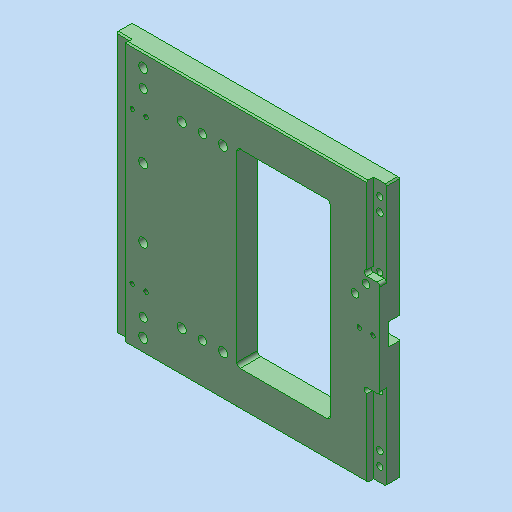
# Autodesk Inventor part: MM0937AN100_G16_103
Saved by Autodesk Inventor 2023.3 (Build 273359000, 359)
## iProperties
Created: 2018-10-25
Part Number: MM0937AN100_G16_103
Material: 1.2842 90MnCrV8
Document SubType Name: Modeling
Designer: Rose
Density: 7.85 g/cm^3
Appearance: Grün-H
Mass: 2925.7 g
Surface Area: 800.514 cm^2
Volume: 372.7 cm^3
Description: =<RBPARTNOTITLE2>
RBMATERIAL: =<Material>
RBMATNO: =<Part Number>
RBPARTMADEOF: Präzi Fl.190 x 15 x 207 (FM)
RBPARTNOTITLE1: manufactured part
RBPARTNOTITLE2: Anfertigungsteil
MaxAbmaße: 190 x 15 x 207 (FM)
RBDRAWINGMISSINGSPEC: --
AnP_Kategorie: 1
RBSURFACE: chemically nickel-coated
AnP_Material: =<Material>
RBSURFACE2: chem. vernickelt
Author: Rose
Keywords: =<RBPARTMADEOF>
Comments: =<RBSURFACE2>
Revision Number: 01
Autodesk Inventor part; units mm, degrees
ref_plane "YZ Plane" through (0, 0, 0) normal (1, 0, 0) x (0, 1, 0)
ref_plane "XZ Plane" through (0, 0, 0) normal (0, 1, 0) x (-1, 0, 0)
ref_plane "XY Plane" through (0, 0, 0) normal (0, 0, 1) x (1, 0, 0)
sketch "Skizze1" plane through (0, 0, 0) normal (0, 0, 1) x (1, 0, 0)
  line L0 (0, 18) -> (0, -3) projected
  line L1 (-97.4, 0) -> (192.4, 0) projected
  line L2 (151, 0) -> (-41, 0)
  line L3 (-41, 0) -> (-41.2, 0.2)
  line L4 (-41.2, 0.2) -> (-56, 0.2)
  line L5 (-56, 0.2) -> (-56, 5.8)
  line L6 (-44, 15) -> (151, 15)
  line L7 (151, 15) -> (151, 0)
  line L8 (-56, 5.8) -> (-44, 5.8)
  line L9 (-44, 5.8) -> (-44, 15)
  line L10 (151, 0) -> (151, 0)
  line L11 (-44, 5.8) -> (-44, 0)
  line L12 (-44, 0) -> (-41, 0)
  dimension "d0" = 15
  dimension "d1" = 151
  dimension "d89" = 45
  dimension "d105" = 90
  dimension "d137" = 41
  dimension "d138" = 44
  dimension "d145" = 56
  dimension "d146" = 9.2
  dimension "d148" = 5.6
  constraints: 22 end point, 4 point on line, 3 perpendicular, 2 parallel, 1 horizontal
  measures "d0" distance between parallel lines of L1 L6
  measures "d1" distance between parallel lines of L7 L0
  measures "d89" angle of L1 L3
  measures "d105" angle of L6 L9
  measures "d137" distance from line of L0 L2.end
  measures "d138" distance from line of L0 L8.end
  measures "d145" distance between parallel lines of L0 L5
  measures "d146" distance between parallel lines of L8 L6
  measures "d148" distance between parallel lines of L4 L8
extrude "Extrusion1" add sketch "Skizze1" along normal mid plane 190 contours L6 L7 L1 L0 | L0 L1 L3 L4 L11 L9 L6 | L1 L11 L4 L3
sketch "Skizze12" plane through (151, 0, 95) normal (1, 0, 0) x (0, 0, -1)
  line L0 (190, 15) -> (0, 15) projected
  line L1 (0, 0) -> (0, 15) projected
  line L2 (190, 0) -> (0, 0) projected
  line L3 (190, 15) -> (190, 0) projected
  line L4 (0, 0) -> (60, 0)
  line L5 (60, 0) -> (60, 5)
  line L6 (60, 5) -> (0, 5)
  line L7 (0, 5) -> (0, 0)
  line L8 (190, 0) -> (130, 0)
  line L9 (130, 0) -> (130, 5)
  line L10 (130, 5) -> (190, 5)
  line L11 (190, 5) -> (190, 0)
  point P0 (95, 0)
  point P1 (130, 0)
  point P2 (60, 0)
  dimension "d155" = 60
  dimension "d156" = 5
  dimension "d157" = 60
  dimension "d158" = 5
  constraints: 16 end point, 4 parallel, 2 horizontal, 2 perpendicular
  measures "d155" distance of L6.end L5.end
  measures "d156" distance of L5.end L4.end
  measures "d157" distance of L9.end L10.end
  measures "d158" distance of L8.end L9.end
extrude "Extrusion5" cut sketch "Skizze12" against normal blind 9.5 contours L3 L2 L9 L10 | L6 L5 L2 L1
sketch "Skizze2" plane through (-56, 15, 95) normal (0, 1, 0) x (1, 0, 0)
  line L0 (246, 95) -> (-27, 95) projected
  line L1 (105.5, 26) -> (168.5, 26)
  line L2 (103, 28.5) -> (103, 161.5)
  line L3 (105.5, 164) -> (168.5, 164)
  line L4 (56, 228) -> (56, -38) projected
  arc A0 (105.5, 164) -> (103, 161.5) centre (105.5, 161.5) ccw
  arc A1 (103, 28.5) -> (105.5, 26) centre (105.5, 28.5) ccw
  arc A2 (171, 161.5) -> (168.5, 164) centre (168.5, 161.5) ccw
  arc A3 (168.5, 26) -> (171, 28.5) centre (168.5, 28.5) ccw
  line L5 (171, 161.5) -> (171, 28.5)
  dimension "d15" = 138
  dimension "d63" = 2.5
  dimension "d117" = 47
  dimension "d120" = 115
  dimension "d124" = 2.5
  constraints: 8 end point, 8 point on circle, 8 tangent, 4 centre point, 2 equal radius, 1 perpendicular, 1 other
  measures "d15" distance between parallel lines of L1 L3
  measures "d63" radius of A2
  measures "d117" distance between parallel lines of L4 L2
  measures "d120" distance between parallel lines of L5 L4
  measures "d124" radius of A1
extrude "Extrusion2" cut sketch "Skizze2" against normal through all
sketch "Skizze3" plane through (-56, 15, -95) normal (0, 1, 0) x (1, 0, 0)
  line L0 (56, 38) -> (56, -228) projected
  line L1 (246, -95) -> (-27, -95) projected
  line L2 (63, -30) -> (93, -30)
  point P0 (93, -160)
  point P1 (63, -160)
  dimension "d22" = 7
  dimension "d23" = 130
  dimension "d118" = 30
  constraints: 2 end point, 2 symmetric about line, 1 coincident, 1 horizontal
  measures "d22" distance from line of L0 L2.start
  measures "d23" distance of point (63, -160) L2.start
  measures "d118" distance of L2.start L2.end
hole "Bohrung1" at (37, 15, -65) at (37, 15, 65) at (7, 15, -65) at (7, 15, 65) direction (0, -1, 0) diameter 6.6 end through all counterbore diameter 11 counterbore depth 6.5
sketch "Skizze4" plane through (-56, 15, -95) normal (0, 1, 0) x (1, 0, 0)
  line L0 (246, -95) -> (-27, -95) projected
  line L1 (56, 38) -> (56, -228) projected
  line L2 (27, -40) -> (37, -40)
  line L3 (27, -150) -> (37, -150)
  line L4 (192, -95) -> (202, -95)
  dimension "d31" = 10
  dimension "d33" = 19
  dimension "d34" = 110
  dimension "d64" = 136
  constraints: 6 coincident, 6 end point, 4 parallel, 1 perpendicular, 1 point on line, 1 symmetric about line
  measures "d31" distance of L2.start L2.end
  measures "d33" distance from line of L1 point (37, -40)
  measures "d34" distance of point (27, -150) point (27, -40)
  measures "d64" distance from line of point (192, -95) L1
hole "Bohrung2" at (-29, 15, -55) at (-19, 15, -55) at (136, 15, 0) at (146, 15, 0) at (-19, 15, 55) at (-29, 15, 55) direction (0, -1, 0) diameter 3.242 end through all thread size "M4x0.7" designation "M4" class "6H" standard "ISO Metric profile"
sketch "Skizze5" plane through (-56, 15, -95) normal (0, 1, 0) x (1, 0, 0)
  line L0 (56, 38) -> (56, -228) projected
  circle A0 centre (37, -40) radius 1.621 projected
  circle A1 centre (192, -95) radius 1.621 projected
  circle A2 centre (37, -150) radius 1.621 projected
  line L1 (37, -40) -> (53, -40) construction
  line L2 (192, -95) -> (176, -95) construction
  line L3 (37, -150) -> (53, -150) construction
  line L4 (12, -158) -> (50, -158)
  line L5 (53, -155) -> (53, -145)
  line L6 (50, -142) -> (12, -142)
  line L7 (179, -103) -> (207, -103)
  line L8 (207, -87) -> (179, -87)
  line L9 (176, -90) -> (176, -100)
  line L10 (12, -48) -> (50, -48)
  line L11 (53, -45) -> (53, -35)
  line L12 (50, -32) -> (12, -32)
  arc A3 (50, -48) -> (53, -45) centre (50, -45) ccw
  arc A4 (53, -35) -> (50, -32) centre (50, -35) ccw
  arc A5 (176, -100) -> (179, -103) centre (179, -100) ccw
  arc A6 (179, -87) -> (176, -90) centre (179, -90) ccw
  arc A7 (53, -145) -> (50, -142) centre (50, -145) ccw
  arc A8 (50, -158) -> (53, -155) centre (50, -155) ccw
  line L13 (207, 0) -> (207, -190) projected
  line L14 (9, -35) -> (9, -45)
  line L15 (9, -145) -> (9, -155)
  arc A9 (12, -32) -> (9, -35) centre (12, -35) ccw
  arc A10 (9, -45) -> (12, -48) centre (12, -45) ccw
  arc A11 (12, -142) -> (9, -145) centre (12, -145) ccw
  arc A12 (9, -155) -> (12, -158) centre (12, -155) ccw
  dimension "d65" = 16
  dimension "d66" = 16
  dimension "d67" = 3
  dimension "d140" = 28
  constraints: 28 end point, 20 point on circle, 20 tangent, 10 centre point, 9 equal radius, 7 perpendicular, 5 parallel, 4 equal length, 3 horizontal, 3 midpoint, 2 point on line, 1 collinear
  measures "d65" distance between parallel lines of L10 L12
  measures "d66" distance of L1.start L1.end
  measures "d67" radius of A3
  measures "d140" distance from line of L14 L1.start
extrude "Extrusion3" cut sketch "Skizze5" against normal blind 8.5
sketch "Skizze6" plane through (-56, 15, -95) normal (0, 1, 0) x (1, 0, 0)
  line L0 (56, 38) -> (56, -228) projected
  line L1 (246, -95) -> (-27, -95) projected
  point P0 (20, -60)
  point P1 (20, -130)
  dimension "d47" = 70
  dimension "d68" = 36
  constraints: 1 symmetric about line
  measures "d47" distance of point (20, -130) point (20, -60)
  measures "d68" distance from line of L0 point (20, -60)
hole "Bohrung3" at (-36, 15, -35) at (-36, 15, 35) direction (0, -1, 0) diameter 9 depth 9 counterbore diameter 17 counterbore depth 5
sketch "Skizze10" plane through (-41, 0, 95) normal (0, -1, 0) x (1, 0, 0)
  line L0 (-42, -95) -> (231, -95) projected
  circle A0 centre (48, -30) radius 3.3 projected
  circle A1 centre (78, -30) radius 3.3 projected
  line L1 (48, -30) -> (78, -30)
  point P0 (63, -30)
  point P1 (63, -160)
  point P2 (12, -10)
  point P3 (63, -30)
  constraints: 2 end point, 1 coincident, 1 horizontal, 1 midpoint, 1 symmetric about line
hole "Bohrung6" at (22, 0, 65) at (22, 0, -65) direction (0, 1, 0) diameter 5.5 end through all counterbore diameter 6 counterbore depth 13
sketch "Skizze11" plane through (-44, 15, 95) normal (0, 1, 0) x (1, 0, 0)
  line L0 (234, 95) -> (-39, 95) projected
  line L1 (44, 228) -> (44, -38) projected
  point P0 (177, 75)
  point P1 (185, 65)
  dimension "d126" = 20
  dimension "d127" = 10
  dimension "d128" = 8
  dimension "d149" = 133
  measures "d126" distance from line of L0 point (177, 75)
  measures "d127" vertical distance of point (185, 65) point (177, 75)
  measures "d128" horizontal distance of point (185, 65) point (177, 75)
  measures "d149" distance from line of point (177, 75) L1
hole "Bohrung7" at (133, 15, 20) at (141, 15, 30) direction (0, -1, 0) diameter 5.5 end through all counterbore diameter 10 counterbore depth 5.5
chamfer "Fase1" distance 1 angle 45 6 edges at (151, 10, 95) (151, 10, -95) (53.5, 15, 95) (48.75, 0, 95) (53.5, 15, -95) (48.75, 0, -95)
chamfer "Fase2" distance 1 angle 45 5 edges at (151, 15, 51) (151, 15, -51) (-44, 15, 0) (-44, 7.5, 95) (-44, 7.5, -95)
chamfer "Fase3" distance 0.5 angle 45 2 edges at (-27.5709, 15, -36.0955) (-27.5709, 15, 36.0955)
sketch "Skizze13" plane through (-43, 15, 94) normal (0, 1, 0) x (1, 0, 0)
  line L0 (194, 0) -> (194, 86) projected
  point P0 (43, 94)
  point P1 (189, 9)
  point P2 (189, 56.6)
  point P3 (189, 131.4)
  point P4 (189, 179)
  dimension "d161" = 5
  dimension "d162" = 37.4
  dimension "d163" = 37.4
  dimension "d164" = 85
  dimension "d165" = 85
  constraints: 3 vertical alignment
  measures "d161" distance from line of point (189, 9) L0
  measures "d162" vertical distance of point (189, 56.6) point (43, 94)
  measures "d163" vertical distance of point (189, 131.4) point (43, 94)
  measures "d164" vertical distance of point (189, 179) point (43, 94)
  measures "d165" vertical distance of point (189, 9) point (43, 94)
hole "Bohrung8" at (146, 15, 85) at (146, 15, 37.4) at (146, 15, -37.4) at (146, 15, -85) direction (0, -1, 0) diameter 4.5 end through all counterbore diameter 8 counterbore depth 4.6 clearance for "Inbusschraube ISO 4762  versenkt" size "M4" standard "ISO"
sketch "Skizze14" plane through (141.5, 5, 35) normal (0, -1, 0) x (1, 0, 0)
  circle A0 centre (4.5, 50) radius 2.25 projected
  point P0 (-141.5, -35)
  point P1 (4.5, 40)
  point P2 (4.5, -110)
  dimension "d173" = 75
  dimension "d174" = 75
  constraints: 2 vertical alignment
  measures "d173" vertical distance of point (4.5, 40) point (-141.5, -35)
  measures "d174" vertical distance of point (4.5, -110) point (-141.5, -35)
hole "Bohrung9" at (146, 5, 75) at (146, 5, -75) direction (0, 1, 0) diameter 4 end through all counterbore diameter 5 counterbore depth 6
fillet "Rundung1" radius 2 2 edges at (151, 2.5, -35) (151, 2.5, 35)
sketch "Skizze15" plane through (-41, 0, 94) normal (0, -1, 0) x (1, 0, 0)
  line L0 (182.5, -59) -> (182.5, 0) projected
  line L1 (182.5, -188) -> (182.5, -129) projected
  circle A0 centre (182.5, -57) radius 2
  circle A1 centre (182.5, -131) radius 2
  point P0 (41, -94)
  point P1 (182.5, -133)
  point P2 (182.5, -55)
  dimension "d183" = 4
  dimension "d184" = 4
  constraints: 2 point on line, 6 other
extrude "Extrusion6" cut sketch "Skizze15" against normal up to surface (5 mm away) contours A0 L0 | A1 L1 picked at (181.8767, -57.2364) picked at (181.9513, -131.3787)
sketch "Skizze17" plane through (-44, 15, -63) normal (0, 1, 0) x (1, 0, 0)
  line L0 (44, 70) -> (44, -196) projected
  line L1 (234, -63) -> (-39, -63) projected
  line L2 (0, 0) -> (0, 31) projected
  point P0 (44, -63)
  point P1 (23, 22)
  point P2 (23, -38)
  point P3 (23, -88)
  point P4 (23, -148)
  dimension "d189" = 23
  dimension "d190" = 50
  dimension "d191" = 170
  constraints: 2 symmetric about line, 2 vertical alignment
  measures "d189" distance from line of point (23, 22) L2
  measures "d190" distance of point (23, -88) point (23, -38)
  measures "d191" distance of point (23, -148) point (23, 22)
hole "Bohrung10" at (-21, 15, -85) at (-21, 15, -25) at (-21, 15, 25) at (-21, 15, 85) direction (0, -1, 0) diameter 6.6 end through all counterbore diameter 11 counterbore depth 6.8 clearance for "Inbusschraube ISO 4762  versenkt" size "M6" standard "ISO"
sketch "Skizze18" plane through (-44, 0, 94) normal (0, -1, 0) x (1, 0, 0)
  line L0 (-39, -94) -> (234, -94) projected
  circle A0 centre (23, -9) radius 3.3 projected
  point P0 (44, -94)
  point P1 (23, -22)
  point P2 (23, -166)
  dimension "d199" = 144
  constraints: 1 symmetric about line, 1 vertical alignment
  measures "d199" distance of point (23, -166) point (23, -22)
hole "Bohrung11" at (-21, 0, 72) at (-21, 0, -72) direction (0, 1, 0) diameter 5.5 end through all counterbore diameter 6 counterbore depth 13
sketch "Skizze19" plane through (-44, 0, 94) normal (0, -1, 0) x (1, 0, 0)
  line L0 (185.5, 1) -> (1, 1) projected
  line L1 (0, -188) -> (0, 0) projected
  line L2 (1, -189) -> (185.5, -189) projected
  line L3 (0, 1) -> (10, 1)
  line L4 (10, 1) -> (10, -189)
  line L5 (10, -189) -> (0, -189)
  line L6 (0, -189) -> (0, 1)
  line L7 (0, 0) -> (185.5, 0) projected
  point P0 (44, -94)
  dimension "d207" = 10
  constraints: 8 end point, 3 collinear, 2 parallel, 1 horizontal, 1 perpendicular
  measures "d207" distance between parallel lines of L1 L4
extrude "Extrusion8" cut sketch "Skizze19" against normal blind 3
chamfer "Fase4" distance 1 angle 45 5 edges at (-44, 3, 0) (-34, 2, 95) (-38.5, 3, 95) (-38.5, 3, -95) (-34, 2, -95)
